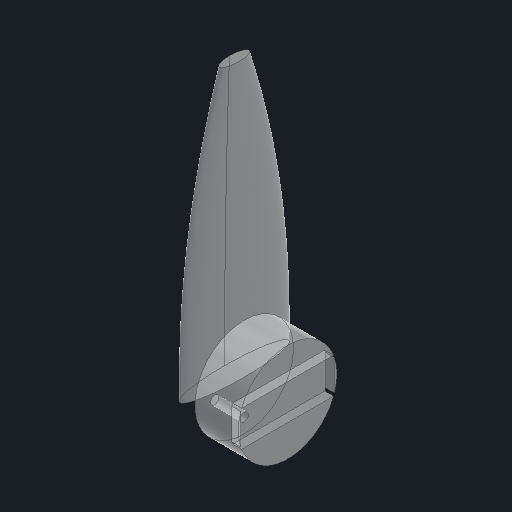
# Autodesk Inventor part: PEN-010L
Saved by Autodesk Inventor 2027.1 (Build 311270010, 270A)
## iProperties
Created: 2026-10-28
Part Number: PEN-010L
Material: PLA 3D Print
Description: Flipper, left, PLA
Document SubType Name: Modeling
Designer: shyan
Mass: 6.33035 g
Surface Area: 33.6188 cm^2
Volume: 5.10512 cm^3
Density: 1.24 g/cm^3
Appearance: Polycarbonate - Clear
Author: shyan
Autodesk Inventor part; units mm, degrees
sketch "fl_root" plane through (0, 0, 0) normal (0, 1, 0) x (-1, 0, 0)
  line L0 (0, 0) -> (60, 0) construction
  line L1 (0, 0) -> (0, 60) construction
  ellipse E0 centre (58, 78) end of major axis (60, 78) minor radius 11
  dimension "d0" = 58
  dimension "d1" = 78
  dimension "d2" = 2
  dimension "d3" = 11
  constraints: 4 end point, 1 centre point, 5 other
  measures "d0" horizontal distance of L0.start E0.centre
  measures "d1" vertical distance of L0.start E0.centre
ref_plane "fl_mid_plane" through (0, 30, 0) normal (0, 1, 0) x (-1, 0, 0)
sketch "fl_mid" plane through (0, 30, 0) normal (0, 1, 0) x (-1, 0, 0)
  line L0 (0, 0) -> (60, 0) construction
  line L1 (0, 0) -> (0, 60) construction
  ellipse E0 centre (58, 78) end of major axis (59.7, 78) minor radius 9
  dimension "d5" = 58
  dimension "d6" = 78
  dimension "d7" = 1.7
  dimension "d8" = 9
  constraints: 4 end point, 1 centre point, 5 other
  measures "d5" horizontal distance of L0.start E0.centre
  measures "d6" vertical distance of L0.start E0.centre
ref_plane "fl_tip_plane" through (0, 55, 0) normal (0, 1, 0) x (-1, 0, 0)
sketch "fl_tip" plane through (0, 55, 0) normal (0, 1, 0) x (-1, 0, 0)
  line L0 (0, 0) -> (60, 0) construction
  line L1 (0, 0) -> (0, 60) construction
  ellipse E0 centre (58, 78) end of major axis (59, 78) minor radius 3
  dimension "d10" = 58
  dimension "d11" = 78
  dimension "d12" = 1
  dimension "d13" = 3
  constraints: 4 end point, 1 centre point, 5 other
  measures "d10" horizontal distance of L0.start E0.centre
  measures "d11" vertical distance of L0.start E0.centre
loft "FlipperLoft" add profiles "fl_root", "fl_mid", "fl_tip"
ref_plane "sk_hub_plane" through (-56, 0, 0) normal (1, 0, 0) x (0, 1, 0)
sketch "sk_hub" plane through (-56, 0, 0) normal (1, 0, 0) x (0, 1, 0)
  line L0 (0, 0) -> (40, 0) construction
  line L1 (0, 0) -> (0, 40) construction
  circle A0 centre (0, 78) radius 10
  dimension "d21" = 20
  dimension "d22" = 78
  constraints: 4 end point, 1 centre point, 1 point on line, 4 other
  measures "d21" diameter of A0
  measures "d22" distance of L0.start A0.centre
extrude "StandoffHub" add sketch "sk_hub" along normal blind 8.82
ref_plane "sk_horn_pocket_plane" through (-47.18, 0, 0) normal (1, 0, 0) x (0, 1, 0)
sketch "sk_horn_pocket" plane through (-47.18, 0, 0) normal (1, 0, 0) x (0, 1, 0)
  line L0 (0, 0) -> (40, 0) construction
  line L1 (0, 0) -> (0, 40) construction
  line L2 (-3.6, 68.5) -> (3.6, 68.5)
  line L3 (3.6, 68.5) -> (3.6, 87.5)
  line L4 (3.6, 87.5) -> (-3.6, 87.5)
  line L5 (-3.6, 87.5) -> (-3.6, 68.5)
  dimension "d26" = 7.2
  dimension "d27" = 19
  dimension "d28" = 68.5
  constraints: 12 end point, 2 parallel, 1 horizontal, 1 perpendicular, 5 other
  measures "d26" distance of L2.start L2.end
  measures "d27" distance of L2.end L3.end
  measures "d28" vertical distance of L0.start L2.start
extrude "HornPocket" cut sketch "sk_horn_pocket" against normal blind 1.8
ref_plane "sk_horn_screw_plane" through (-48.98, 0, 0) normal (1, 0, 0) x (0, 1, 0)
sketch "sk_horn_screw" plane through (-48.98, 0, 0) normal (1, 0, 0) x (0, 1, 0)
  line L0 (0, 0) -> (40, 0) construction
  line L1 (0, 0) -> (0, 40) construction
  circle A0 centre (0, 85) radius 0.85
  dimension "d32" = 1.7
  dimension "d33" = 85
  constraints: 4 end point, 1 centre point, 1 point on line, 4 other
  measures "d32" diameter of A0
  measures "d33" distance of L0.start A0.centre
extrude "HornScrew" cut sketch "sk_horn_screw" against normal blind 6
ref_plane "pl_flipZ" through (0, 0, 78) normal (0, 0, 1) x (1, 0, 0)
equation "\"d0\" = flip_midX"
equation "\"d1\" = Z_flip"
equation "\"d2\" = 0.5 * flip_t"
equation "\"d3\" = 0.5 * flip_w"
equation "\"d5\" = flip_midX"
equation "\"d6\" = Z_flip"
equation "\"d7\" = 0.5 * flip_mid_t"
equation "\"d8\" = 0.5 * flip_mid_w"
equation "\"d10\" = flip_midX"
equation "\"d11\" = Z_flip"
equation "\"d12\" = 0.5 * flip_tip_t"
equation "\"d13\" = 0.5 * flip_tip_w"
equation "\"d21\" = hub_d"
equation "\"d22\" = Z_flip"
equation "\"d23\" = flip_planeX - hub_Xi"
equation "\"d26\" = horn_hub"
equation "\"d27\" = horn_arm"
equation "\"d28\" = Z_flip - 0.5 * horn_arm"
equation "\"d29\" = horn_T"
equation "\"d32\" = m2_pilot"
equation "\"d33\" = Z_flip + horn_screw_z"
equation "\"d34\" = ins_L"
equation "\"clr\" = 0.3"
equation "\"wall\" = 2.4"
equation "\"sv_L\" = 22.8"
equation "\"sv_W\" = 12.2"
equation "\"sv_H\" = 22.7"
equation "\"sv_full\" = 28.5"
equation "\"sv_tab\" = 32.5"
equation "\"sv_tabT\" = 2.5"
equation "\"sv_tabZ\" = 15.5"
equation "\"sv_pitch\" = 27.5"
equation "\"sv_shaft\" = 5.9"
equation "\"sv_dome\" = 12"
equation "\"sv_domeH\" = 3.3"
equation "\"sv_spline\" = 4.8"
equation "\"m2_pilot\" = 1.7"
equation "\"horn_len\" = 31.5"
equation "\"horn_hub\" = 7.2"
equation "\"horn_tip\" = 4.5"
equation "\"horn_T\" = 1.8"
equation "\"horn_hubH\" = 3.8"
equation "\"ins_d\" = 4"
equation "\"ins_L\" = 6"
equation "\"m3\" = 3.4"
equation "\"nut_af\" = 5.8"
equation "\"hip_x\" = 26"
equation "\"plate_T\" = 5"
equation "\"col_H\" = 16"
equation "\"tray_T\" = 3"
equation "\"bodyW0\" = 96"
equation "\"bodyW35\" = 106"
equation "\"bodyD35\" = 86"
equation "\"bodyW85\" = 92"
equation "\"bodyD85\" = 74"
equation "\"bodyW112\" = 64"
equation "\"bodyD112\" = 56"
equation "\"Z_sec1\" = 35"
equation "\"Z_sec2\" = 85"
equation "\"Z_sec3\" = 112"
equation "\"Z_flip\" = 78"
equation "\"Z_bridge\" = 98"
equation "\"bat_W\" = 77"
equation "\"bat_D\" = 41"
equation "\"bat_H\" = 21"
equation "\"esp_W\" = 55"
equation "\"esp_D\" = 28"
equation "\"esp_H\" = 13"
equation "\"pcb_D\" = 38"
equation "\"pcb_T\" = 1.6"
equation "\"bk_D\" = 22"
equation "\"df_W\" = 49"
equation "\"df_D\" = 32"
equation "\"df_H\" = 12"
equation "\"sw_W\" = 21"
equation "\"sw_D\" = 15"
equation "\"sw_H\" = 25"
equation "\"usb_cut_W\" = 12"
equation "\"usb_cut_H\" = 7"
equation "\"usb_pitch\" = 28"
equation "\"flip_len\" = 55"
equation "\"flip_w\" = 22"
equation "\"flip_t\" = 4"
equation "\"flip_mid_w\" = 18"
equation "\"flip_mid_t\" = 3.4"
equation "\"flip_tip_w\" = 6"
equation "\"flip_tip_t\" = 2"
equation "\"flip_proud\" = 2"
equation "\"flip_body_max\" = 53"
equation "\"flip_gap\" = 3"
equation "\"hub_d\" = 20"
equation "\"hornhub_clr\" = 2"
equation "\"horn_arm\" = 19"
equation "\"horn_screw_z\" = 7"
equation "\"spline_tip\" = halfW_flip + flip_proud"
equation "\"flip_planeX\" = flip_body_max + flip_gap"
equation "\"flip_midX\" = flip_planeX + 0.5 * flip_t"
equation "\"hub_Xi\" = spline_tip - horn_T"
equation "\"d9\" = flip_len"
equation "\"d20\" = -flip_planeX"
equation "\"d25\" = -hub_Xi"
equation "\"d31\" = -horn_T - hub_Xi"
equation "\"d36\" = Z_flip"
equation "\"halfW_flip\" = 46.98"
body "Solid1"
